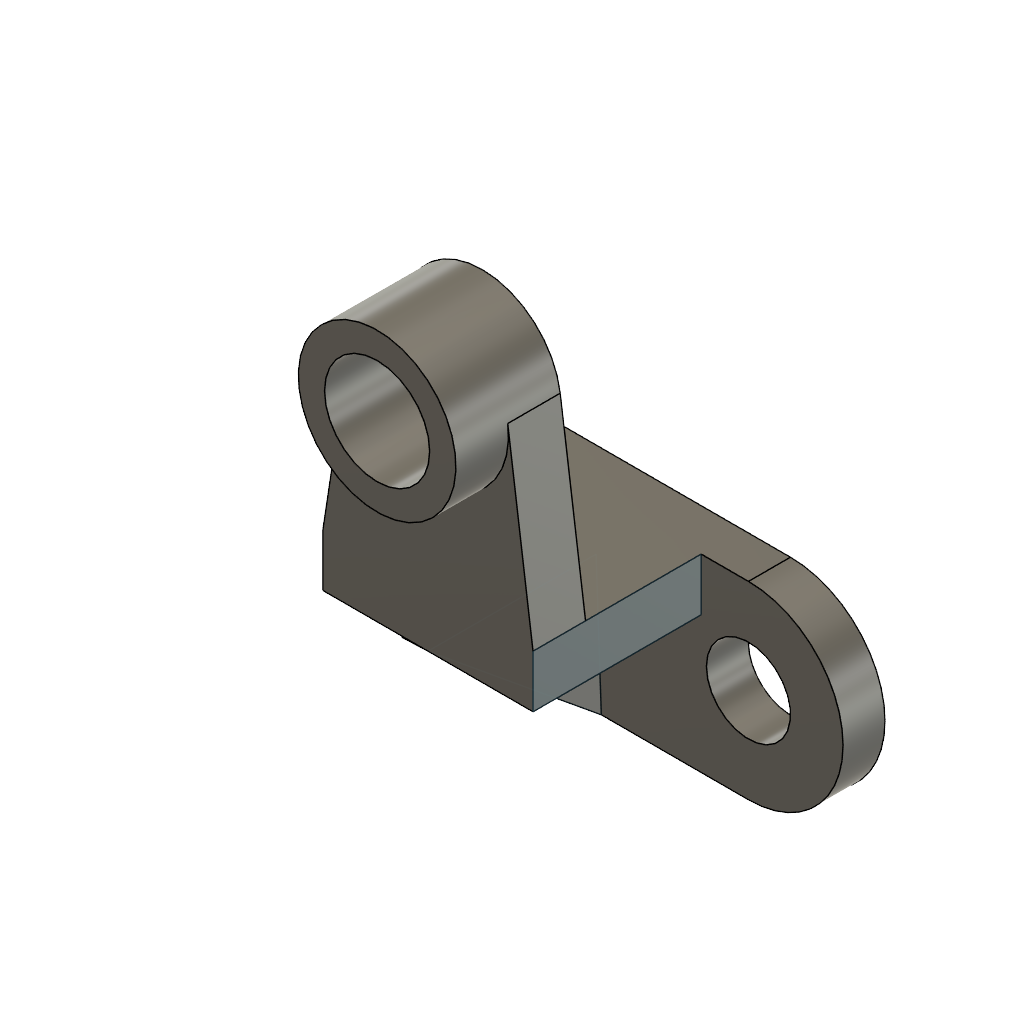
NITHISH 26015028 exercise .2.2 (Autodesk Fusion 360 design; units mm, degrees)
part number: 2026-10-06-15-12-10-312
Autodesk Fusion 360 part; units mm, degrees
sketch "Sketch1" plane through (0, 0, 0) normal (0, 0, 1) x (1, 0, 0)
  circle A0 centre (-28, 0) radius 8
  line L0 (0, 0) -> (0, 85)
  circle A1 centre (28, 0) radius 8
  line L1 (-28, 18) -> (28, 18)
  line L2 (-28, -18) -> (28, -18)
  arc A2 (-28, 18) -> (-28, -18) centre (-28, 0) ccw
  arc A3 (28, -18) -> (28, 18) centre (28, 0) ccw
  dimension "d1" = 16
  dimension "d2" = 36
  dimension "d3" = 28
  constraint concentric A0 A2
  constraint coincident L0.start origin
  constraint vertical L0
  constraint symmetric A0 L0 A1
  constraint symmetric L0 A2 A3
  constraint perpendicular L0 L1
  constraint horizontal L2
  constraint tangent L2 A2
  constraint tangent L1 A2
  measures "d1" diameter of A0
  measures "d2" diameter of A2
  measures "d3" distance of L0.start A0.centre
extrude "Extrude1" add sketch "Sketch1" along normal blind 8 makes body 1
sketch "Sketch2" plane through (0, 0, 8) normal (0, 0, 1) x (1, 0, 0)
  circle A0 centre (28, 0) radius 8
  circle A1 centre (-28, 0) radius 8
  arc A2 (-28, 18) -> (-28, -18) centre (-28, 0) ccw
  line L0 (-28, -18) -> (28, -18)
  arc A3 (28, -18) -> (28, 18) centre (28, 0) ccw
  line L1 (28, 18) -> (-28, 18)
  line L2 (-21, 18) -> (19, 18)
  line L3 (19, 18) -> (19, 8)
  line L4 (19, 8) -> (-21, 8)
  line L5 (-21, 8) -> (-21, 18)
  dimension "d6" = 10
  constraint horizontal L2
  constraint vertical L3
  constraint horizontal L4
  constraint vertical L5
  constraint coincident L1 L2.start
  measures "d6" distance of L2.start L4.end
extrude "Extrude2" add sketch "Sketch2" along normal blind 32 contours L1 L2 L3 L4 L5 bodies 1
sketch "Sketch3" plane through (0, 0, 40) normal (0, 0, 1) x (1, 0, 0)
  line L0 (-21, 8) -> (19, 8)
  line L1 (19, 8) -> (19, 18)
  line L2 (19, 18) -> (-21, 18)
  line L3 (-21, 18) -> (-21, 8)
  circle A0 centre (-0.6728, 51.0866) radius 10
  line L4 (-21, 18) -> (-15.4945, 53.3922)
  line L5 (19, 18) -> (14.1884, 53.1225)
  arc A1 (14.1884, 53.1225) -> (-15.4945, 53.3922) centre (-0.6728, 51.0866) ccw
  dimension "d9" = 20
  dimension "d10" = 30
  constraint concentric A0 A1
  constraint coincident L2.end L3.start
  constraint coincident L1.end L2.start
  constraint tangent L4 A1
  constraint tangent L5 A1
  measures "d9" diameter of A0
  measures "d10" diameter of A1
extrude "Extrude3" add sketch "Sketch3" against normal blind 10 contours L2 L4 L5 A1 bodies 1
sketch "Sketch4" plane through (0, 0, 40) normal (0, 0, 1) x (1, 0, 0)
  circle A0 centre (-0.6728, 51.0866) radius 10
  line L0 (-21, 8) -> (19, 8)
  line L1 (19, 8) -> (19, 18)
  line L2 (19, 18) -> (14.1884, 53.1225)
  arc A1 (14.1884, 53.1225) -> (-15.4945, 53.3922) centre (-0.6728, 51.0866) ccw
  line L3 (-15.4945, 53.3922) -> (-21, 18)
  line L4 (-21, 18) -> (-21, 8)
  circle A2 centre (-0.6728, 51.0866) radius 15
  dimension "d13" = 30
  constraint concentric A0 A2
  measures "d13" diameter of A2
extrude "Extrude4" add sketch "Sketch4" along normal blind 10 contours A1 A2 bodies 1
sketch "Sketch5" plane through (0, 0, 0) normal (1, 0, 0) x (0, 0, -1)
sketch "Sketch6" plane through (19, 0, 0) normal (1, 0, 0) x (0, 0, -1)
  line L0 (-8, 8) -> (-8, 18)
  line L1 (-8, 18) -> (-30, 18)
  line L2 (-30, 18) -> (-40, 18)
  line L3 (-40, 18) -> (-40, 8)
  line L4 (-40, 8) -> (-8, 8)
sketch "Sketch7" plane through (0, 8, 0) normal (0, -1, 0) x (1, 0, 0)
  line L0 (-21, 8) -> (19, 8)
  line L1 (19, 8) -> (19, 40)
  line L2 (19, 40) -> (-21, 40)
  line L3 (-21, 40) -> (-21, 8)
  line L4 (-28, 8, 26) -> (28, 8, 26)
  line L5 (-1, 40, 0) -> (0, 8, 26)
  line L6 (0, 8, 26) -> (-1, 8, 0)
  line L7 (-1, 40) -> (-1, 8)
  constraint midpoint L2 L7.start
  constraint midpoint L0 L7.end
extrude "Extrude5" add sketch "Sketch7" against normal blind 5 separate body contours L5 L6 L7 in plane through (-0.9985, 7.9616, 0) normal (0.999261, 0.038433, 0) makes body 2
